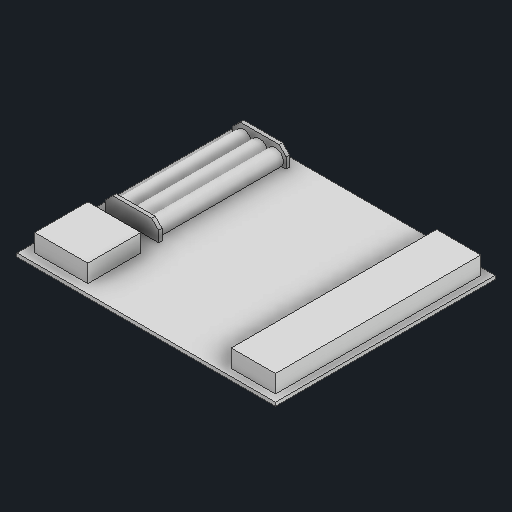
# Autodesk Inventor part: 7_5_1_toit_arriere
Saved by Autodesk Inventor 2026 (Build 300175000, 175)
## iProperties
Created: 2025-06-21
Part Number: 7_5_1_toit_arriere
Material: Generic
Document SubType Name: Modeling
Designer: remg9
Density: 1 g/cm^3
Appearance: Default
Author: remg9
Autodesk Inventor part; units mm, degrees
ref_plane "YZ Plane" through (0, 0, 0) normal (1, 0, 0) x (0, 1, 0)
ref_plane "XZ Plane" through (0, 0, 0) normal (0, 1, 0) x (-1, 0, 0)
ref_plane "XY Plane" through (0, 0, 0) normal (0, 0, 1) x (1, 0, 0)
sketch "Sketch1" plane through (0, 0, 0) normal (0, 1, 0) x (-1, 0, 0)
  line L0 (0, 0) -> (146, 0)
  line L1 (146, 0) -> (146, -124)
  line L2 (146, -124) -> (0, -124)
  line L3 (0, -124) -> (0, 0)
  dimension "d0" = 146
  dimension "d1" = 124
  constraints: 8 end point, 2 parallel, 1 horizontal, 1 perpendicular
  measures "d0" distance of L1.end L2.end
  measures "d1" distance between parallel lines of L0 L2
extrude "Extrusion1" add sketch "Sketch1" along normal blind 2
sketch "Sketch2" plane through (0, 2, 0) normal (0, 1, 0) x (1, 0, 0)
  line L0 (-29, 4) -> (-4, 4)
  line L1 (-4, 4) -> (-4, 120)
  line L2 (-4, 120) -> (-29, 120)
  line L3 (-29, 120) -> (-29, 4)
  line L4 (0, 0) -> (0, 124) projected
  line L5 (0, 124) -> (-146, 124) projected
  line L6 (-146, 0) -> (0, 0) projected
  dimension "d4" = 4
  dimension "d5" = 4
  dimension "d6" = 4
  dimension "d7" = 25
  constraints: 8 end point, 2 parallel, 1 horizontal, 1 perpendicular
  measures "d4" distance between parallel lines of L4 L1
  measures "d5" distance between parallel lines of L5 L2
  measures "d6" distance between parallel lines of L6 L0
  measures "d7" distance between parallel lines of L1 L3
extrude "Extrusion2" add sketch "Sketch2" along normal blind 10
sketch "Sketch3" plane through (0, 2, 0) normal (0, 1, 0) x (1, 0, 0)
  line L0 (-141, 35) -> (-111, 35)
  line L1 (-111, 35) -> (-111, 5)
  line L2 (-111, 5) -> (-141, 5)
  line L3 (-141, 5) -> (-141, 35)
  line L4 (-141, 47) -> (-111, 47)
  line L5 (-111, 47) -> (-111, 45)
  line L6 (-111, 45) -> (-141, 45)
  line L7 (-141, 45) -> (-141, 47)
  line L8 (-141, 119) -> (-111, 119)
  line L9 (-111, 119) -> (-111, 117)
  line L10 (-111, 117) -> (-141, 117)
  line L11 (-141, 117) -> (-141, 119)
  line L12 (-146, 124) -> (-146, 0) projected
  line L13 (0, 124) -> (-146, 124) projected
  line L14 (-146, 0) -> (0, 0) projected
  dimension "d10" = 5
  dimension "d11" = 2
  dimension "d12" = 30
  dimension "d13" = 5
  dimension "d14" = 70
  dimension "d15" = 30
  dimension "d16" = 5
  constraints: 24 end point, 6 parallel, 4 point on line, 3 horizontal, 3 perpendicular, 1 collinear
  measures "d10" distance between parallel lines of L12 L11
  measures "d11" distance of L8.end L9.end
  measures "d12" distance of L8.start L8.end
  measures "d13" distance between parallel lines of L13 L8
  measures "d14" distance between parallel lines of L4 L10
  measures "d15" distance of L2.end L0.start
  measures "d16" distance between parallel lines of L14 L2
extrude "Extrusion3" add sketch "Sketch3" along normal blind 10
sketch "Sketch4" plane through (-141, 2, -117) normal (0, 0, 1) x (1, 0, 0)
  circle A0 centre (6, 3) radius 4.5
  circle A1 centre (15, 3) radius 4.5
  circle A2 centre (24, 3) radius 4.5
  line L0 (6, 3) -> (24, 3) construction
  line L1 (30, 10) -> (0, 10) construction
  line L2 (0, 0) -> (0, 10) construction
  line L3 (0, 0) -> (30, 0) projected
  line L4 (15, 10) -> (15, 0) construction
  point P0 (141, -2)
  point P1 (1.9169, 4.8916)
  point P2 (19.5, 3)
  point P3 (10.5, 3)
  point P4 (15, 3)
  dimension "d21" = 9
  dimension "d19" = 9
  dimension "d20" = 9
  dimension "d22" = 9
  dimension "d23" = 9
  dimension "d26" = 3
  constraints: 4 end point, 4 midpoint, 2 centre point, 1 coincident, 1 parallel, 1 point on line, 3 other
  measures "d19" distance of A1.centre A2.centre
  measures "d20" distance of L0.start A1.centre
  measures "d22" diameter of A1
  measures "d23" diameter of A2
  measures "d26" distance between parallel lines of L3 L0
extrude "Extrusion4" add sketch "Sketch4" along normal blind 70 contours A0 L3 | A1 L3 | L3 A0 | A2 L3 | L3 A1 | L3 A2
chamfer "Chamfer1" distance 4 angle 45 4 edges at (-111, 12, -46) (-141, 12, -46) (-111, 12, -118) (-141, 12, -118)
body "Solid1"
